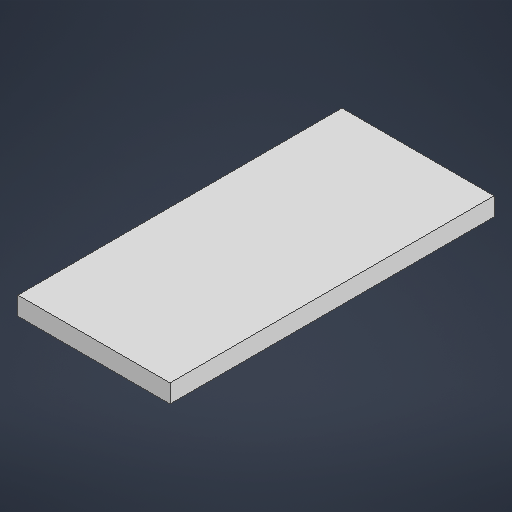
# Autodesk Inventor part: lampe3
Saved by Autodesk Inventor 2026 (Build 300175000, 175)
## iProperties
Created: 2026-10-28
Part Number: lampe3
Material: Generic
Document SubType Name: Modeling
Designer: alexp
Density: 1 g/cm^3
Appearance: Default
Author: alexp
Autodesk Inventor part; units mm, degrees
ref_plane "YZ Plane" through (0, 0, 0) normal (1, 0, 0) x (0, 1, 0)
ref_plane "XZ Plane" through (0, 0, 0) normal (0, 1, 0) x (-1, 0, 0)
ref_plane "XY Plane" through (0, 0, 0) normal (0, 0, 1) x (1, 0, 0)
sketch "Sketch1" plane through (0, 0, 0) normal (0, 1, 0) x (-1, 0, 0)
  line L0 (15.6532, 44.5828) -> (-9.3468, 44.5828)
  line L1 (-9.3468, 44.5828) -> (-9.3468, -8.6712)
  line L2 (-9.3468, -8.6712) -> (15.6532, -8.6712)
  line L3 (15.6532, -8.6712) -> (15.6532, 44.5828)
  point P0 (0, 0)
  dimension "d0" = 25
  dimension "d1" = 53.254
  constraints: 8 end point, 2 parallel, 1 horizontal, 1 perpendicular
  measures "d0" distance between parallel lines of L1 L3
  measures "d1" distance between parallel lines of L0 L2
extrude "Extrusion1" add sketch "Sketch1" along normal blind 3
body "Solid1"
